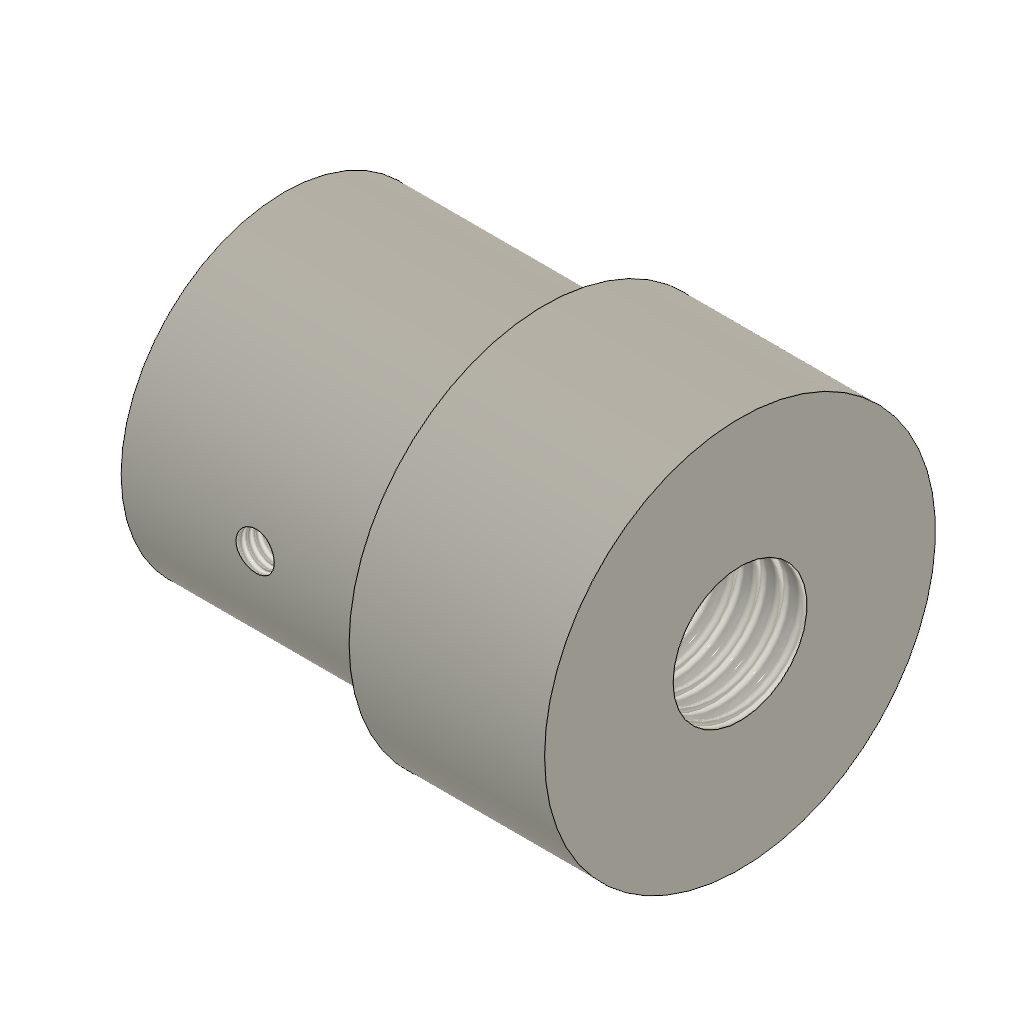
Acople_tornillo (Autodesk Fusion 360 design; units mm, degrees)
Autodesk Fusion 360 part; units mm, degrees
note: some values were not read from the file. Set by a fixed rule: which face or edge a step refers to.
sketch "Boceto1" plane through (0, 0, 0) normal (1, 0, 0) x (0, 0, -1)
  circle A0 centre (0, 0) radius 6.5
  circle A1 centre (0, 0) radius 12.5
  dimension "d1" = 13
  dimension "d2" = 25
  constraint coincident A0.centre A1.centre
  constraint concentric A0 A1
  measures "d1" diameter of A0
  measures "d2" diameter of A1
extrude "Extruir1" add sketch "Boceto1" along normal blind 20
sketch "Boceto2" plane through (20, 0, 0) normal (1, 0, 0) x (0, 0, -1)
  circle A0 centre (0, 0) radius 6.5
  circle A1 centre (0, 0) radius 12.5
  circle A2 centre (0, 0) radius 6.3
  circle A3 centre (0, 0) radius 15
  dimension "d5" = 12.6
  dimension "d6" = 30
  constraint coincident A0.centre A1.centre
  measures "d5" diameter of A2
  measures "d6" diameter of A3
extrude "Extruir2" add sketch "Boceto2" along normal blind 15 contours A0 | A1 | A3
thread "Rosca1" "ISO Metric profile 12.0 M12x1.75 M12x1.75 6H" major diameter 12.2265 minor diameter 10.2735 pitch 1.75 angle 60 resizes the face on face at (30, -0.6273, -6.2687)
ref_plane "PlanoDeObra1" through (12.091, 0, 12.5) normal (0, 0, 1) x (0, 1, 0)
sketch "Boceto3" plane through (0, 0, 12.5) normal (0, 0, 1) x (1, 0, 0)
  circle A0 centre (10.2873, 0) radius 1.925
  dimension "d12" = 3.85
  measures "d12" diameter of A0
extrude "Extruir3" cut sketch "Boceto3" against normal blind 35
thread "Rosca2" "ISO Metric profile 3.5 M3.5x0.6 M3.5x0.6 6H" major diameter 3.5995 minor diameter 2.93 pitch 0.6 angle 60 resizes the face on face at (8.3711, -0.1836, -10.4971)
thread "Rosca3" "ISO Metric profile 3.5 M3.5x0.6 M3.5x0.6 6H" major diameter 3.5995 minor diameter 2.93 pitch 0.6 angle 60 resizes the face on face at (8.3697, -0.168, 10.4977)
equation "d12 = ( 1.925 * 2 ) * 1 mm"
